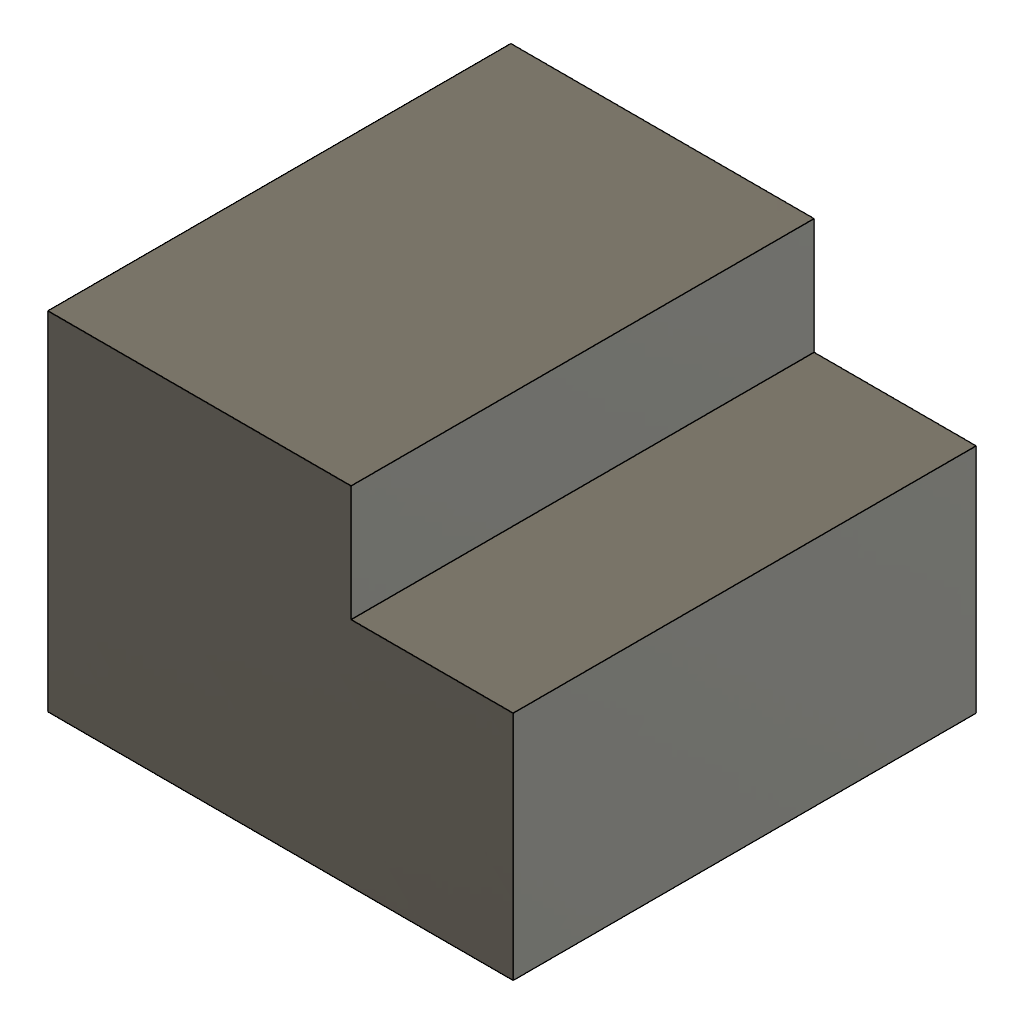
FlushUpper (Autodesk Fusion 360 design; units mm, degrees)
part number: 2026-11-22-12-52-57-436
Autodesk Fusion 360 part; units mm, degrees
sketch "Base sketch" plane through (0, 0, 0) normal (0, 0, 1) x (1, 0, 0)
  line L0 (-10, 0) -> (10.1, 0)
  line L1 (10.1, 0) -> (10.1, 15)
  line L2 (10.1, 15) -> (-10, 15)
  line L3 (-10, 15) -> (-10, 0)
extrude "Base" add sketch "Base sketch" along normal blind 20
sketch "Corner sketch" plane through (0, 0, 0) normal (0, 0, 1) x (1, 0, 0)
  line L0 (3.1, 10) -> (10.1, 10)
  line L1 (10.1, 10) -> (10.1, 20)
  line L2 (10.1, 20) -> (3.1, 20)
  line L3 (3.1, 20) -> (3.1, 10)
extrude "Corner" cut sketch "Corner sketch" along normal blind 20
